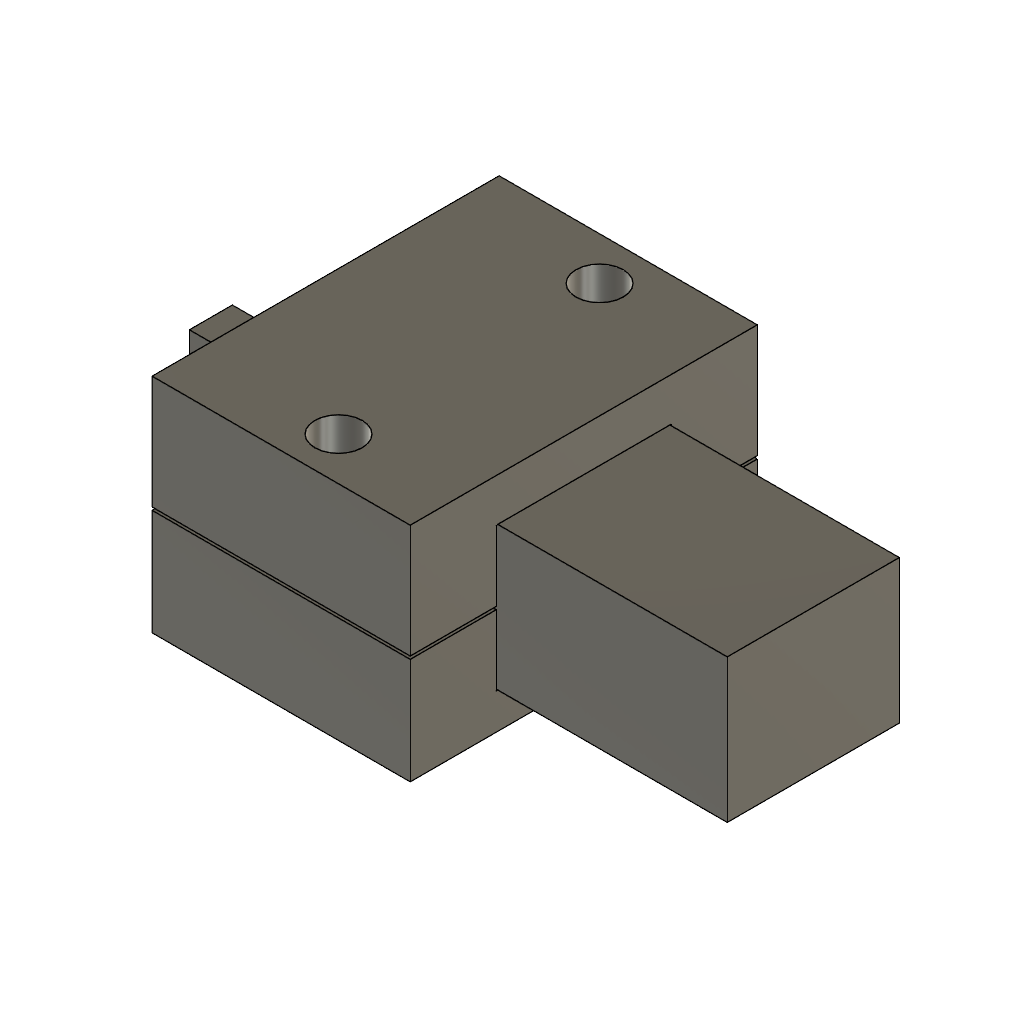
n20_holder (Autodesk Fusion 360 design; units mm, degrees)
Autodesk Fusion 360 part; units mm, degrees
sketch "cradle block" plane through (0, 0, 0) normal (0, 0, 1) x (1, 0, 0) in component "N20 holder cradle"
  line L0 (0, -12.1) -> (18, -12.1)
  line L1 (18, -12.1) -> (18, 12.1)
  line L2 (18, 12.1) -> (0, 12.1)
  line L3 (0, 12.1) -> (0, -12.1)
extrude "Extrude1" add sketch "cradle block" along normal blind 7.9 makes body 1 in component "N20 holder cradle"
ref_plane "WorkPlane1" through (0, 0, 3) normal (0, 0, 1) x (1, 0, 0) in component "N20 holder cradle"
sketch "cradle pocket" plane through (0, 0, 3) normal (0, 0, 1) x (1, 0, 0) in component "N20 holder cradle"
  line L0 (2, -6.1) -> (18, -6.1)
  line L1 (18, -6.1) -> (18, 6.1)
  line L2 (18, 6.1) -> (2, 6.1)
  line L3 (2, 6.1) -> (2, -6.1)
extrude "Extrude2" cut sketch "cradle pocket" along normal blind 4.9 bodies 1 in component "N20 holder cradle"
ref_plane "WorkPlane2" through (0, 0, 5.4) normal (0, 0, 1) x (1, 0, 0) in component "N20 holder cradle"
sketch "cradle shaft notch" plane through (0, 0, 5.4) normal (0, 0, 1) x (1, 0, 0) in component "N20 holder cradle"
  line L0 (0, -2.5) -> (2, -2.5)
  line L1 (2, -2.5) -> (2, 2.5)
  line L2 (2, 2.5) -> (0, 2.5)
  line L3 (0, 2.5) -> (0, -2.5)
extrude "Extrude3" cut sketch "cradle shaft notch" along normal blind 2.5 bodies 1 in component "N20 holder cradle"
sketch "cradle screw holes" plane through (0, 0, 0) normal (0, 0, 1) x (1, 0, 0) in component "N20 holder cradle"
  circle A0 centre (10, 9.1) radius 1.65
  circle A1 centre (10, -9.1) radius 1.65
extrude "Extrude4" cut sketch "cradle screw holes" along normal blind 7.9 bodies 1 in component "N20 holder cradle"
sketch "cap block" plane through (0, 0, 0) normal (0, 0, 1) x (1, 0, 0) in component "N20 holder cap"
  line L0 (0, -12.1) -> (18, -12.1)
  line L1 (18, -12.1) -> (18, 12.1)
  line L2 (18, 12.1) -> (0, 12.1)
  line L3 (0, 12.1) -> (0, -12.1)
extrude "Extrude1'" add sketch "cap block" along normal blind 7.4 separate body makes body 2 in component "N20 holder cap"
ref_plane "WorkPlane1" through (0, 0, 2.5) normal (0, 0, 1) x (1, 0, 0) in component "N20 holder cap"
sketch "cap pocket" plane through (0, 0, 2.5) normal (0, 0, 1) x (1, 0, 0) in component "N20 holder cap"
  line L0 (2, -6.1) -> (18, -6.1)
  line L1 (18, -6.1) -> (18, 6.1)
  line L2 (18, 6.1) -> (2, 6.1)
  line L3 (2, 6.1) -> (2, -6.1)
extrude "Extrude2'" cut sketch "cap pocket" along normal blind 4.9 bodies 2 in component "N20 holder cap"
ref_plane "WorkPlane2" through (0, 0, 4.9) normal (0, 0, 1) x (1, 0, 0) in component "N20 holder cap"
sketch "cap shaft notch" plane through (0, 0, 4.9) normal (0, 0, 1) x (1, 0, 0) in component "N20 holder cap"
  line L0 (0, -2.5) -> (2, -2.5)
  line L1 (2, -2.5) -> (2, 2.5)
  line L2 (2, 2.5) -> (0, 2.5)
  line L3 (0, 2.5) -> (0, -2.5)
extrude "Extrude3'" cut sketch "cap shaft notch" along normal blind 2.5 bodies 2 in component "N20 holder cap"
sketch "cap screw holes" plane through (0, 0, 0) normal (0, 0, 1) x (1, 0, 0) in component "N20 holder cap"
  circle A0 centre (10, 9.1) radius 1.65
  circle A1 centre (10, -9.1) radius 1.65
extrude "Extrude4'" cut sketch "cap screw holes" along normal blind 7.4 bodies 2 in component "N20 holder cap"
ref_plane "WorkPlane1" through (0, 0, -13) normal (0, 0, 1) x (1, 0, 0) in component "N20 motor (ref, do not print)"
sketch "body" plane through (0, 0, -13) normal (0, 0, 1) x (1, 0, 0) in component "N20 motor (ref, do not print)"
  line L0 (2, -6) -> (34, -6)
  line L1 (34, -6) -> (34, 6)
  line L2 (34, 6) -> (2, 6)
  line L3 (2, 6) -> (2, -6)
extrude "Extrude1''" add sketch "body" along normal blind 10 separate body makes body 3 in component "N20 motor (ref, do not print)"
ref_plane "WorkPlane2" through (0, 0, -9.5) normal (0, 0, 1) x (1, 0, 0) in component "N20 motor (ref, do not print)"
sketch "shaft" plane through (0, 0, -9.5) normal (0, 0, 1) x (1, 0, 0) in component "N20 motor (ref, do not print)"
  line L0 (-8, -1.5) -> (2, -1.5)
  line L1 (2, -1.5) -> (2, 1.5)
  line L2 (2, 1.5) -> (-8, 1.5)
  line L3 (-8, 1.5) -> (-8, -1.5)
extrude "Extrude2''" add sketch "shaft" along normal blind 3 separate body makes body 4 in component "N20 motor (ref, do not print)"
component "N20 holder cradle" placed x (1, 0, 0) y (0, -1, 0) z (0, 0, -1) at (0, 0, 0)
component "N20 holder cap" placed x (1, 0, 0) y (0, 1, 0) z (0, 0, 1) at (0, 0, -15.5)
component "N20 motor (ref, do not print)" placed x (1, 0, 0) y (0, 1, 0) z (0, 0, 1) at (0, 0, 0)
